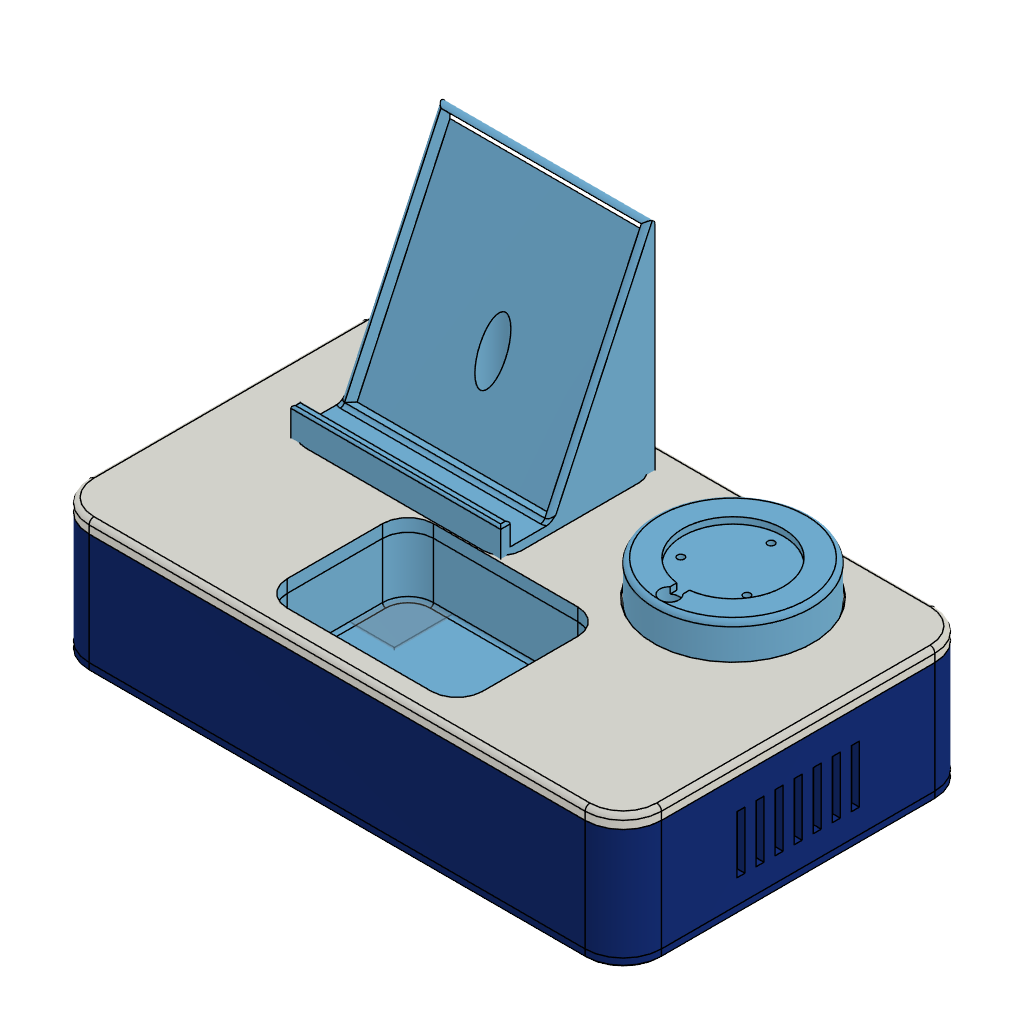
Multi_charge (Autodesk Fusion 360 design; units mm, degrees)
part number: 2026-11-17-23-31-15-888
part number: 2026-11-18-01-23-41-298
part number: 2026-11-18-01-23-42-263
part number: 2026-11-18-01-23-42-966
part number: 2026-11-18-01-29-00-402
part number: 2026-11-18-01-29-01-069
part number: 2026-11-18-01-54-52-643
part number: 2026-11-18-01-54-53-349
part number: 2026-11-18-01-54-56-501
description: REFERENCE ONLY - envelopes, not real STEP models. Do not print.
part number: 2026-11-18-01-54-56-940
description: REFERENCE ONLY - clearance keep-out volumes. Do not print.
part number: 2026-11-18-01-54-57-566
Autodesk Fusion 360 part; units mm, degrees
ref_plane "WorkPlane1" through (0, 0, 2.5) normal (0, 0, 1) x (1, 0, 0) in component "Base_Enclosure"
sketch "Base Outline" plane through (0, 0, 2.5) normal (0, 0, 1) x (1, 0, 0) in component "Base_Enclosure"
  line L0 (-78, -55) -> (78, -55)
  line L1 (90, -43) -> (90, 43)
  line L2 (78, 55) -> (-78, 55)
  line L3 (-90, 43) -> (-90, -43)
  arc A0 (78, -55) -> (90, -43) centre (78, -43) ccw
  arc A1 (90, 43) -> (78, 55) centre (78, 43) ccw
  arc A2 (-78, 55) -> (-90, 43) centre (-78, 43) ccw
  arc A3 (-90, -43) -> (-78, -55) centre (-78, -43) ccw
extrude "Base Extrude" add sketch "Base Outline" along normal blind 35 makes body 1 in component "Base_Enclosure"
shell "Base Shell" thickness 2.4 removed faces 2 at (26, -18.3333, 2.5) at (26, -18.3333, 37.5) on bodies 1 in component "Base_Enclosure"
ref_plane "WorkPlane2" through (0, 0, 8) normal (0, 0, 1) x (1, 0, 0) in component "Base_Enclosure"
sketch "Rib Layout" plane through (0, 0, 8) normal (0, 0, 1) x (1, 0, 0) in component "Base_Enclosure"
  line L0 (-59, -53.8) -> (-57, -53.8)
  line L1 (-57, -53.8) -> (-57, 53.8)
  line L2 (-57, 53.8) -> (-59, 53.8)
  line L3 (-59, 53.8) -> (-59, -53.8)
  line L4 (57, -53.8) -> (59, -53.8)
  line L5 (59, -53.8) -> (59, 53.8)
  line L6 (59, 53.8) -> (57, 53.8)
  line L7 (57, 53.8) -> (57, -53.8)
  line L8 (-88.8, -44) -> (-58, -44)
  line L9 (-58, -44) -> (-58, -42)
  line L10 (-58, -42) -> (-88.8, -42)
  line L11 (-88.8, -42) -> (-88.8, -44)
  line L12 (-88.8, 42) -> (-58, 42)
  line L13 (-58, 42) -> (-58, 44)
  line L14 (-58, 44) -> (-88.8, 44)
  line L15 (-88.8, 44) -> (-88.8, 42)
  line L16 (58, -44) -> (88.8, -44)
  line L17 (88.8, -44) -> (88.8, -42)
  line L18 (88.8, -42) -> (58, -42)
  line L19 (58, -42) -> (58, -44)
  line L20 (58, 42) -> (88.8, 42)
  line L21 (88.8, 42) -> (88.8, 44)
  line L22 (88.8, 44) -> (58, 44)
  line L23 (58, 44) -> (58, 42)
extrude "Structural Ribs" add sketch "Rib Layout" along normal blind 25.5 bodies 1 in component "Base_Enclosure"
ref_plane "WorkPlane1" through (0, 0, 37.5) normal (0, 0, 1) x (1, 0, 0) in component "Upper_Platform"
sketch "Platform Outline" plane through (0, 0, 37.5) normal (0, 0, 1) x (1, 0, 0) in component "Upper_Platform"
  line L0 (-78, -55) -> (78, -55)
  line L1 (90, -43) -> (90, 43)
  line L2 (78, 55) -> (-78, 55)
  line L3 (-90, 43) -> (-90, -43)
  arc A0 (78, -55) -> (90, -43) centre (78, -43) ccw
  arc A1 (90, 43) -> (78, 55) centre (78, 43) ccw
  arc A2 (-78, 55) -> (-90, 43) centre (-78, 43) ccw
  arc A3 (-90, -43) -> (-78, -55) centre (-78, -43) ccw
extrude "Platform Plate" add sketch "Platform Outline" along normal blind 4 separate body makes body 2 in component "Upper_Platform"
sketch "Locating Lip" plane through (0, 0, 37.5) normal (0, 0, 1) x (1, 0, 0) in component "Upper_Platform"
  line L0 (-78, -52.3) -> (78, -52.3)
  line L1 (87.3, -43) -> (87.3, 43)
  line L2 (78, 52.3) -> (-78, 52.3)
  line L3 (-87.3, 43) -> (-87.3, -43)
  arc A0 (78, -52.3) -> (87.3, -43) centre (78, -43) ccw
  arc A1 (87.3, 43) -> (78, 52.3) centre (78, 43) ccw
  arc A2 (-78, 52.3) -> (-87.3, 43) centre (-78, 43) ccw
  arc A3 (-87.3, -43) -> (-78, -52.3) centre (-78, -43) ccw
  line L4 (-78, -50.7) -> (78, -50.7)
  line L5 (85.7, -43) -> (85.7, 43)
  line L6 (78, 50.7) -> (-78, 50.7)
  line L7 (-85.7, 43) -> (-85.7, -43)
  arc A4 (78, -50.7) -> (85.7, -43) centre (78, -43) ccw
  arc A5 (85.7, 43) -> (78, 50.7) centre (78, 43) ccw
  arc A6 (-78, 50.7) -> (-85.7, 43) centre (-78, 43) ccw
  arc A7 (-85.7, -43) -> (-78, -50.7) centre (-78, -43) ccw
extrude "Locating Lip Extrude" add sketch "Locating Lip" against normal blind 3 bodies 2 in component "Upper_Platform"
fillet "Platform Edge Fillet" radius 1.5 64 edges at (-86.4853, -51.4853, 41.5) (0, -55, 41.5) (86.4853, -51.4853, 41.5) (90, 0, 41.5) (86.4853, 51.4853, 41.5) (0, 55, 41.5) (-86.4853, 51.4853, 41.5) (-90, 0, 41.5) (0, -55, 41.5) (86.4853, -51.4853, 41.5) (90, 0, 41.5) (86.4853, 51.4853, 41.5) (0, 55, 41.5) (-86.4853, 51.4853, 41.5) (-90, 0, 41.5) (-86.4853, -51.4853, 41.5) (86.4853, -51.4853, 41.5) (90, 0, 41.5) (86.4853, 51.4853, 41.5) (0, 55, 41.5) (-86.4853, 51.4853, 41.5) (-90, 0, 41.5) (-86.4853, -51.4853, 41.5) (0, -55, 41.5) (90, 0, 41.5) (86.4853, 51.4853, 41.5) (0, 55, 41.5) (-86.4853, 51.4853, 41.5) (-90, 0, 41.5) (-86.4853, -51.4853, 41.5) (0, -55, 41.5) (86.4853, -51.4853, 41.5) (86.4853, 51.4853, 41.5) (0, 55, 41.5) (-86.4853, 51.4853, 41.5) (-90, 0, 41.5) (-86.4853, -51.4853, 41.5) (0, -55, 41.5) (86.4853, -51.4853, 41.5) (90, 0, 41.5) (0, 55, 41.5) (-86.4853, 51.4853, 41.5) (-90, 0, 41.5) (-86.4853, -51.4853, 41.5) (0, -55, 41.5) (86.4853, -51.4853, 41.5) (90, 0, 41.5) (86.4853, 51.4853, 41.5) (-86.4853, 51.4853, 41.5) (-90, 0, 41.5) (-86.4853, -51.4853, 41.5) (0, -55, 41.5) (86.4853, -51.4853, 41.5) (90, 0, 41.5) (86.4853, 51.4853, 41.5) (0, 55, 41.5) (-90, 0, 41.5) (-86.4853, -51.4853, 41.5) (0, -55, 41.5) (86.4853, -51.4853, 41.5) (90, 0, 41.5) (86.4853, 51.4853, 41.5) (0, 55, 41.5) (-86.4853, 51.4853, 41.5) on bodies 2 in component "Upper_Platform"
ref_plane "WorkPlane2" through (0, 0, 41.5) normal (0, 0, 1) x (1, 0, 0) in component "Upper_Platform"
sketch "Charging Zones (phone, watch, earbuds)" plane through (0, 0, 41.5) normal (0, 0, 1) x (1, 0, 0) in component "Upper_Platform"
  line L0 (-63.5, -1.5) -> (-7.5, -1.5)
  line L1 (-1.5, 4.5) -> (-1.5, 41.5)
  line L2 (-7.5, 47.5) -> (-63.5, 47.5)
  line L3 (-69.5, 41.5) -> (-69.5, 4.5)
  arc A0 (-7.5, -1.5) -> (-1.5, 4.5) centre (-7.5, 4.5) ccw
  arc A1 (-1.5, 41.5) -> (-7.5, 47.5) centre (-7.5, 41.5) ccw
  arc A2 (-63.5, 47.5) -> (-69.5, 41.5) centre (-63.5, 41.5) ccw
  arc A3 (-69.5, 4.5) -> (-63.5, -1.5) centre (-63.5, 4.5) ccw
  circle A4 centre (44.5, 25) radius 25
  line L4 (-22, -44) -> (22, -44)
  line L5 (30, -36) -> (30, -14)
  line L6 (22, -6) -> (-22, -6)
  line L7 (-30, -14) -> (-30, -36)
  arc A5 (22, -44) -> (30, -36) centre (22, -36) ccw
  arc A6 (30, -14) -> (22, -6) centre (22, -14) ccw
  arc A7 (-22, -6) -> (-30, -14) centre (-22, -14) ccw
  arc A8 (-30, -36) -> (-22, -44) centre (-22, -36) ccw
extrude "Charging Zone Recesses" cut sketch "Charging Zones (phone, watch, earbuds)" against normal blind 1.2 bodies 2 in component "Upper_Platform"
sketch "Cover Outline" plane through (0, 0, 0) normal (0, 0, 1) x (1, 0, 0) in component "Bottom_Cover"
  line L0 (-78, -55) -> (78, -55)
  line L1 (90, -43) -> (90, 43)
  line L2 (78, 55) -> (-78, 55)
  line L3 (-90, 43) -> (-90, -43)
  arc A0 (78, -55) -> (90, -43) centre (78, -43) ccw
  arc A1 (90, 43) -> (78, 55) centre (78, 43) ccw
  arc A2 (-78, 55) -> (-90, 43) centre (-78, 43) ccw
  arc A3 (-90, -43) -> (-78, -55) centre (-78, -43) ccw
extrude "Cover Plate" add sketch "Cover Outline" along normal blind 2.5 separate body makes body 3 in component "Bottom_Cover"
ref_plane "WorkPlane1" through (0, 0, 2.5) normal (0, 0, 1) x (1, 0, 0) in component "Bottom_Cover"
sketch "Locating Lip (2)" plane through (0, 0, 2.5) normal (0, 0, 1) x (1, 0, 0) in component "Bottom_Cover"
  line L0 (-78, -52.3) -> (78, -52.3)
  line L1 (87.3, -43) -> (87.3, 43)
  line L2 (78, 52.3) -> (-78, 52.3)
  line L3 (-87.3, 43) -> (-87.3, -43)
  arc A0 (78, -52.3) -> (87.3, -43) centre (78, -43) ccw
  arc A1 (87.3, 43) -> (78, 52.3) centre (78, 43) ccw
  arc A2 (-78, 52.3) -> (-87.3, 43) centre (-78, 43) ccw
  arc A3 (-87.3, -43) -> (-78, -52.3) centre (-78, -43) ccw
  line L4 (-78, -50.7) -> (78, -50.7)
  line L5 (85.7, -43) -> (85.7, 43)
  line L6 (78, 50.7) -> (-78, 50.7)
  line L7 (-85.7, 43) -> (-85.7, -43)
  arc A4 (78, -50.7) -> (85.7, -43) centre (78, -43) ccw
  arc A5 (85.7, 43) -> (78, 50.7) centre (78, 43) ccw
  arc A6 (-78, 50.7) -> (-85.7, 43) centre (-78, 43) ccw
  arc A7 (-85.7, -43) -> (-78, -50.7) centre (-78, -43) ccw
extrude "Locating Lip Extrude'" add sketch "Locating Lip (2)" along normal blind 3 bodies 3 in component "Bottom_Cover"
sketch "PCB Standoffs (placeholder envelope)" plane through (0, 0, 2.5) normal (0, 0, 1) x (1, 0, 0) in component "Bottom_Cover"
  circle A0 centre (-46, -31) radius 3.5
  circle A1 centre (-46, -31) radius 1.25
  circle A2 centre (-46, 31) radius 3.5
  circle A3 centre (-46, 31) radius 1.25
  circle A4 centre (46, -31) radius 3.5
  circle A5 centre (46, -31) radius 1.25
  circle A6 centre (46, 31) radius 3.5
  circle A7 centre (46, 31) radius 1.25
extrude "PCB Standoffs" add sketch "PCB Standoffs (placeholder envelope)" along normal blind 8 bodies 3 in component "Bottom_Cover"
ref_plane "WorkPlane1" through (-83, 0, 0) normal (1, 0, 0) x (0, 1, 0) in component "Phone_Holder"
sketch "Holder Side Profile" plane through (-83, 0, 0) normal (1, 0, 0) x (0, 0, -1) in component "Phone_Holder"
  line L0 (-40.3, -1.0742) -> (-40.3, 47.5)
  line L1 (-40.3, 47.5) -> (-115.3, 47.5)
  line L2 (-115.3, 47.5) -> (-43.3, 13.9258)
  line L3 (-43.3, 13.9258) -> (-43.3, 1.9258)
  line L4 (-43.3, 1.9258) -> (-50.3, 1.9258)
  line L5 (-50.3, 1.9258) -> (-50.3, -1.0742)
  line L6 (-50.3, -1.0742) -> (-40.3, -1.0742)
extrude "Holder Body" add sketch "Holder Side Profile" along normal blind 66 separate body makes body 4 in component "Phone_Holder"
fillet "Support Face Fillet" radius 1.5 4 edges at (-83, 30.7129, 79.3) (-50, 13.9258, 43.3) (-17, 30.7129, 79.3) (-50, 47.5, 115.3) on bodies 4 in component "Phone_Holder"
fillet "Retaining Lip Fillet" radius 0.75 4 edges at (-83, 0.4258, 50.3) (-50, -1.0742, 50.3) (-17, 0.4258, 50.3) (-50, 1.9258, 50.3) on bodies 4 in component "Phone_Holder"
sketch "MagSafe Pocket" plane through (0, -5.1463, 2.3997) normal (0, -0.906308, 0.422618) x (0, -0.422618, -0.906308) in component "Phone_Holder"
  line L0 (-46.0841, -81.5) -> (-46.0841, -18.5)
  line L1 (-46.0841, -18.5) -> (-117.8056, -18.5)
  line L2 (-117.8056, -18.5) -> (-117.8056, -81.5)
  line L3 (-117.8056, -81.5) -> (-46.0841, -81.5)
  circle A0 centre (-81.9448, -50) radius 27.75
extrude "MagSafe Pocket Cut" cut sketch "MagSafe Pocket" against normal blind 4.37 contours L0 L1 L2 L3 | A0 bodies 4 in component "Phone_Holder"
ref_plane "WorkPlane2" through (0, 0, 115.3) normal (0, 0, 1) x (1, 0, 0) in component "Phone_Holder"
sketch "Cable Channel" plane through (0, 0, 115.3) normal (0, 0, 1) x (1, 0, 0) in component "Phone_Holder"
  circle A0 centre (-50, 29.4851) radius 4
extrude "Cable Channel (1)" cut sketch "Cable Channel" against normal blind 75 bodies 4 in component "Phone_Holder"
sketch "Phone Cable Port" plane through (0, 0, 41.5) normal (0, 0, 1) x (1, 0, 0) in component "Upper_Platform"
  circle A0 centre (-35.5, 29.4851) radius 4
extrude "Phone Cable Port (1)" cut sketch "Phone Cable Port" against normal blind 4 bodies 2 in component "Upper_Platform"
ref_plane "WorkPlane1" through (0, 0, 40.3) normal (0, 0, 1) x (1, 0, 0) in component "Watch_Holder"
sketch "Watch Pad Outline" plane through (0, 0, 40.3) normal (0, 0, 1) x (1, 0, 0) in component "Watch_Holder"
  circle A0 centre (30, 25) radius 24.5
extrude "Watch Pad" add sketch "Watch Pad Outline" along normal blind 12 separate body makes body 5 in component "Watch_Holder"
fillet "Pad Top Fillet" radius 1.5 1 edges at (7.158, 16.1404, 52.3) on bodies 5 in component "Watch_Holder"
ref_plane "WorkPlane2" through (0, 0, 52.3) normal (0, 0, 1) x (1, 0, 0) in component "Watch_Holder"
sketch "Charging Surface Recess" plane through (0, 0, 52.3) normal (0, 0, 1) x (1, 0, 0) in component "Watch_Holder"
  circle A0 centre (30, 25) radius 15.81
extrude "Charging Surface Recess (1)" cut sketch "Charging Surface Recess" against normal blind 2 bodies 5 in component "Watch_Holder"
sketch "Cable Groove" plane through (0, 0, 52.3) normal (0, 0, 1) x (1, 0, 0) in component "Watch_Holder"
  line L0 (28, 5) -> (32, 5)
  line L1 (32, 5) -> (32, 11.19)
  line L2 (32, 11.19) -> (28, 11.19)
  line L3 (28, 11.19) -> (28, 5)
extrude "Cable Groove Cut" cut sketch "Cable Groove" against normal blind 2 bodies 5 in component "Watch_Holder"
sketch "Cable Passage" plane through (0, 0, 52.3) normal (0, 0, 1) x (1, 0, 0) in component "Watch_Holder"
  circle A0 centre (30, 5) radius 3
extrude "Cable Passage (1)" cut sketch "Cable Passage" against normal blind 12 bodies 5 in component "Watch_Holder"
ref_plane "WorkPlane3" through (0, 0, 50.3) normal (0, 0, 1) x (1, 0, 0) in component "Watch_Holder"
sketch "M2 Mounting Holes" plane through (0, 0, 50.3) normal (0, 0, 1) x (1, 0, 0) in component "Watch_Holder"
  circle A0 centre (30, 37) radius 1.1
  circle A1 centre (19.6077, 19) radius 1.1
  circle A2 centre (40.3923, 19) radius 1.1
extrude "M2 Mounting Holes (1)" cut sketch "M2 Mounting Holes" against normal blind 6 bodies 5 in component "Watch_Holder"
sketch "Watch Cable Port" plane through (0, 0, 41.5) normal (0, 0, 1) x (1, 0, 0) in component "Upper_Platform"
  circle A0 centre (44.5, 5) radius 3
extrude "Watch Cable Port (1)" cut sketch "Watch Cable Port" against normal blind 4 bodies 2 in component "Upper_Platform"
ref_plane "WorkPlane1" through (0, 0, 17) normal (0, 0, 1) x (1, 0, 0) in component "Earbuds_Compartment"
sketch "Tray Outer" plane through (0, 0, 17) normal (0, 0, 1) x (1, 0, 0) in component "Earbuds_Compartment"
  line L0 (1.3, -49.6) -> (46.7, -49.6)
  line L1 (56.3, -40) -> (56.3, -10)
  line L2 (46.7, -0.4) -> (1.3, -0.4)
  line L3 (-8.3, -10) -> (-8.3, -40)
  arc A0 (46.7, -49.6) -> (56.3, -40) centre (46.7, -40) ccw
  arc A1 (56.3, -10) -> (46.7, -0.4) centre (46.7, -10) ccw
  arc A2 (1.3, -0.4) -> (-8.3, -10) centre (1.3, -10) ccw
  arc A3 (-8.3, -40) -> (1.3, -49.6) centre (1.3, -40) ccw
extrude "Tray Outer (1)" add sketch "Tray Outer" along normal blind 20.5 separate body makes body 6 in component "Earbuds_Compartment"
ref_plane "WorkPlane2" through (0, 0, 37.5) normal (0, 0, 1) x (1, 0, 0) in component "Earbuds_Compartment"
sketch "Case Pocket" plane through (0, 0, 37.5) normal (0, 0, 1) x (1, 0, 0) in component "Earbuds_Compartment"
  line L0 (1.3, -48) -> (46.7, -48)
  line L1 (54.7, -40) -> (54.7, -10)
  line L2 (46.7, -2) -> (1.3, -2)
  line L3 (-6.7, -10) -> (-6.7, -40)
  arc A0 (46.7, -48) -> (54.7, -40) centre (46.7, -40) ccw
  arc A1 (54.7, -10) -> (46.7, -2) centre (46.7, -10) ccw
  arc A2 (1.3, -2) -> (-6.7, -10) centre (1.3, -10) ccw
  arc A3 (-6.7, -40) -> (1.3, -48) centre (1.3, -40) ccw
extrude "Case Pocket Cut" cut sketch "Case Pocket" against normal blind 18.5 bodies 6 in component "Earbuds_Compartment"
fillet "Pocket Floor Fillet" radius 1 64 edges at (-4.3569, -45.6569, 19) (-6.7, -25, 19) (-4.3569, -4.3431, 19) (24, -2, 19) (52.3569, -4.3431, 19) (54.7, -25, 19) (52.3569, -45.6569, 19) (24, -48, 19) (24, -48, 19) (-4.3569, -45.6569, 19) (-6.7, -25, 19) (-4.3569, -4.3431, 19) (24, -2, 19) (52.3569, -4.3431, 19) (54.7, -25, 19) (52.3569, -45.6569, 19) (52.3569, -45.6569, 19) (24, -48, 19) (-4.3569, -45.6569, 19) (-6.7, -25, 19) (-4.3569, -4.3431, 19) (24, -2, 19) (52.3569, -4.3431, 19) (54.7, -25, 19) (54.7, -25, 19) (52.3569, -45.6569, 19) (24, -48, 19) (-4.3569, -45.6569, 19) (-6.7, -25, 19) (-4.3569, -4.3431, 19) (24, -2, 19) (52.3569, -4.3431, 19) (52.3569, -4.3431, 19) (54.7, -25, 19) (52.3569, -45.6569, 19) (24, -48, 19) (-4.3569, -45.6569, 19) (-6.7, -25, 19) (-4.3569, -4.3431, 19) (24, -2, 19) (24, -2, 19) (52.3569, -4.3431, 19) (54.7, -25, 19) (52.3569, -45.6569, 19) (24, -48, 19) (-4.3569, -45.6569, 19) (-6.7, -25, 19) (-4.3569, -4.3431, 19) (-4.3569, -4.3431, 19) (24, -2, 19) (52.3569, -4.3431, 19) (54.7, -25, 19) (52.3569, -45.6569, 19) (24, -48, 19) (-4.3569, -45.6569, 19) (-6.7, -25, 19) (-6.7, -25, 19) (-4.3569, -4.3431, 19) (24, -2, 19) (52.3569, -4.3431, 19) (54.7, -25, 19) (52.3569, -45.6569, 19) (24, -48, 19) (-4.3569, -45.6569, 19) on bodies 6 in component "Earbuds_Compartment"
sketch "Earbuds Case Opening" plane through (0, 0, 41.5) normal (0, 0, 1) x (1, 0, 0) in component "Upper_Platform"
  line L0 (-22.7, -48) -> (22.7, -48)
  line L1 (30.7, -40) -> (30.7, -10)
  line L2 (22.7, -2) -> (-22.7, -2)
  line L3 (-30.7, -10) -> (-30.7, -40)
  arc A0 (22.7, -48) -> (30.7, -40) centre (22.7, -40) ccw
  arc A1 (30.7, -10) -> (22.7, -2) centre (22.7, -10) ccw
  arc A2 (-22.7, -2) -> (-30.7, -10) centre (-22.7, -10) ccw
  arc A3 (-30.7, -40) -> (-22.7, -48) centre (-22.7, -40) ccw
extrude "Earbuds Case Opening Cut" cut sketch "Earbuds Case Opening" against normal blind 4 bodies 2 in component "Upper_Platform"
ref_plane "WorkPlane1" through (0, 0, 2.5) normal (0, 0, 1) x (1, 0, 0) in component "PCB_Supports"
ref_plane "WorkPlane2" through (0, 0, 12.85) normal (0, 0, 1) x (1, 0, 0) in component "PCB_Supports"
sketch "QI_Support_1 Post" plane through (0, 0, 2.5) normal (0, 0, 1) x (1, 0, 0) in component "PCB_Supports"
  line L0 (11, -39.6) -> (19, -39.6)
  line L1 (19, -39.6) -> (19, -31)
  line L2 (19, -31) -> (11, -31)
  line L3 (11, -31) -> (11, -39.6)
extrude "QI_Support_1 Post (1)" add sketch "QI_Support_1 Post" along normal blind 10.35 separate body makes body 7 in component "PCB_Supports"
sketch "QI_Support_1 Edge Guide" plane through (0, 0, 12.85) normal (0, 0, 1) x (1, 0, 0) in component "PCB_Supports"
  line L0 (10, -37.5) -> (20, -37.5)
  line L1 (20, -37.5) -> (20, -36.3)
  line L2 (20, -36.3) -> (10, -36.3)
  line L3 (10, -36.3) -> (10, -37.5)
extrude "QI_Support_1 Guide" add sketch "QI_Support_1 Edge Guide" along normal blind 2 bodies 7 in component "PCB_Supports"
sketch "QI_Support_2 Post" plane through (0, 0, 2.5) normal (0, 0, 1) x (1, 0, 0) in component "PCB_Supports"
  line L0 (29, -39.6) -> (37, -39.6)
  line L1 (37, -39.6) -> (37, -31)
  line L2 (37, -31) -> (29, -31)
  line L3 (29, -31) -> (29, -39.6)
extrude "QI_Support_2 Post (1)" add sketch "QI_Support_2 Post" along normal blind 10.35 separate body makes body 8 in component "PCB_Supports"
sketch "QI_Support_2 Edge Guide" plane through (0, 0, 12.85) normal (0, 0, 1) x (1, 0, 0) in component "PCB_Supports"
  line L0 (28, -37.5) -> (38, -37.5)
  line L1 (38, -37.5) -> (38, -36.3)
  line L2 (38, -36.3) -> (28, -36.3)
  line L3 (28, -36.3) -> (28, -37.5)
extrude "QI_Support_2 Guide" add sketch "QI_Support_2 Edge Guide" along normal blind 2 bodies 8 in component "PCB_Supports"
sketch "QI_Support_3 Post" plane through (0, 0, 2.5) normal (0, 0, 1) x (1, 0, 0) in component "PCB_Supports"
  line L0 (11, -19) -> (19, -19)
  line L1 (19, -19) -> (19, -10.4)
  line L2 (19, -10.4) -> (11, -10.4)
  line L3 (11, -10.4) -> (11, -19)
extrude "QI_Support_3 Post (1)" add sketch "QI_Support_3 Post" along normal blind 10.35 separate body makes body 9 in component "PCB_Supports"
sketch "QI_Support_3 Edge Guide" plane through (0, 0, 12.85) normal (0, 0, 1) x (1, 0, 0) in component "PCB_Supports"
  line L0 (10, -13.7) -> (20, -13.7)
  line L1 (20, -13.7) -> (20, -12.5)
  line L2 (20, -12.5) -> (10, -12.5)
  line L3 (10, -12.5) -> (10, -13.7)
extrude "QI_Support_3 Guide" add sketch "QI_Support_3 Edge Guide" along normal blind 2 bodies 9 in component "PCB_Supports"
sketch "QI_Support_4 Post" plane through (0, 0, 2.5) normal (0, 0, 1) x (1, 0, 0) in component "PCB_Supports"
  line L0 (29, -19) -> (37, -19)
  line L1 (37, -19) -> (37, -10.4)
  line L2 (37, -10.4) -> (29, -10.4)
  line L3 (29, -10.4) -> (29, -19)
extrude "QI_Support_4 Post (1)" add sketch "QI_Support_4 Post" along normal blind 10.35 separate body makes body 10 in component "PCB_Supports"
sketch "QI_Support_4 Edge Guide" plane through (0, 0, 12.85) normal (0, 0, 1) x (1, 0, 0) in component "PCB_Supports"
  line L0 (28, -13.7) -> (38, -13.7)
  line L1 (38, -13.7) -> (38, -12.5)
  line L2 (38, -12.5) -> (28, -12.5)
  line L3 (28, -12.5) -> (28, -13.7)
extrude "QI_Support_4 Guide" add sketch "QI_Support_4 Edge Guide" along normal blind 2 bodies 10 in component "PCB_Supports"
sketch "QI_Support_5 Post" plane through (0, 0, 2.5) normal (0, 0, 1) x (1, 0, 0) in component "PCB_Supports"
  line L0 (0.4, -35) -> (9, -35)
  line L1 (9, -35) -> (9, -27)
  line L2 (9, -27) -> (0.4, -27)
  line L3 (0.4, -27) -> (0.4, -35)
extrude "QI_Support_5 Post (1)" add sketch "QI_Support_5 Post" along normal blind 10.35 separate body makes body 11 in component "PCB_Supports"
sketch "QI_Support_5 Edge Guide" plane through (0, 0, 12.85) normal (0, 0, 1) x (1, 0, 0) in component "PCB_Supports"
  line L0 (2.5, -36) -> (3.7, -36)
  line L1 (3.7, -36) -> (3.7, -26)
  line L2 (3.7, -26) -> (2.5, -26)
  line L3 (2.5, -26) -> (2.5, -36)
extrude "QI_Support_5 Guide" add sketch "QI_Support_5 Edge Guide" along normal blind 2 bodies 11 in component "PCB_Supports"
sketch "QI_Support_6 Post" plane through (0, 0, 2.5) normal (0, 0, 1) x (1, 0, 0) in component "PCB_Supports"
  line L0 (39, -23) -> (47.6, -23)
  line L1 (47.6, -23) -> (47.6, -15)
  line L2 (47.6, -15) -> (39, -15)
  line L3 (39, -15) -> (39, -23)
extrude "QI_Support_6 Post (1)" add sketch "QI_Support_6 Post" along normal blind 10.35 separate body makes body 12 in component "PCB_Supports"
sketch "QI_Support_6 Edge Guide" plane through (0, 0, 12.85) normal (0, 0, 1) x (1, 0, 0) in component "PCB_Supports"
  line L0 (44.3, -24) -> (45.5, -24)
  line L1 (45.5, -24) -> (45.5, -14)
  line L2 (45.5, -14) -> (44.3, -14)
  line L3 (44.3, -14) -> (44.3, -24)
extrude "QI_Support_6 Guide" add sketch "QI_Support_6 Edge Guide" along normal blind 2 bodies 12 in component "PCB_Supports"
ref_plane "WorkPlane3" through (0, 0, 2.5) normal (0, 0, 1) x (1, 0, 0) in component "PCB_Supports"
ref_plane "WorkPlane4" through (0, 0, 7.5) normal (0, 0, 1) x (1, 0, 0) in component "PCB_Supports"
sketch "PD_Support_1 Post" plane through (0, 0, 2.5) normal (0, 0, 1) x (1, 0, 0) in component "PCB_Supports"
  line L0 (-47, -21.6) -> (-39, -21.6)
  line L1 (-39, -21.6) -> (-39, -13)
  line L2 (-39, -13) -> (-47, -13)
  line L3 (-47, -13) -> (-47, -21.6)
extrude "PD_Support_1 Post (1)" add sketch "PD_Support_1 Post" along normal blind 5 separate body makes body 13 in component "PCB_Supports"
sketch "PD_Support_1 Edge Guide" plane through (0, 0, 7.5) normal (0, 0, 1) x (1, 0, 0) in component "PCB_Supports"
  line L0 (-48, -19.5) -> (-38, -19.5)
  line L1 (-38, -19.5) -> (-38, -18.3)
  line L2 (-38, -18.3) -> (-48, -18.3)
  line L3 (-48, -18.3) -> (-48, -19.5)
extrude "PD_Support_1 Guide" add sketch "PD_Support_1 Edge Guide" along normal blind 2 bodies 13 in component "PCB_Supports"
sketch "PD_Support_2 Post" plane through (0, 0, 2.5) normal (0, 0, 1) x (1, 0, 0) in component "PCB_Supports"
  line L0 (-31, -21.6) -> (-23, -21.6)
  line L1 (-23, -21.6) -> (-23, -13)
  line L2 (-23, -13) -> (-31, -13)
  line L3 (-31, -13) -> (-31, -21.6)
extrude "PD_Support_2 Post (1)" add sketch "PD_Support_2 Post" along normal blind 5 separate body makes body 14 in component "PCB_Supports"
sketch "PD_Support_2 Edge Guide" plane through (0, 0, 7.5) normal (0, 0, 1) x (1, 0, 0) in component "PCB_Supports"
  line L0 (-32, -19.5) -> (-22, -19.5)
  line L1 (-22, -19.5) -> (-22, -18.3)
  line L2 (-22, -18.3) -> (-32, -18.3)
  line L3 (-32, -18.3) -> (-32, -19.5)
extrude "PD_Support_2 Guide" add sketch "PD_Support_2 Edge Guide" along normal blind 2 bodies 14 in component "PCB_Supports"
sketch "PD_Support_3 Post" plane through (0, 0, 2.5) normal (0, 0, 1) x (1, 0, 0) in component "PCB_Supports"
  line L0 (-47, -3) -> (-39, -3)
  line L1 (-39, -3) -> (-39, 5.6)
  line L2 (-39, 5.6) -> (-47, 5.6)
  line L3 (-47, 5.6) -> (-47, -3)
extrude "PD_Support_3 Post (1)" add sketch "PD_Support_3 Post" along normal blind 5 separate body makes body 15 in component "PCB_Supports"
sketch "PD_Support_3 Edge Guide" plane through (0, 0, 7.5) normal (0, 0, 1) x (1, 0, 0) in component "PCB_Supports"
  line L0 (-48, 2.3) -> (-38, 2.3)
  line L1 (-38, 2.3) -> (-38, 3.5)
  line L2 (-38, 3.5) -> (-48, 3.5)
  line L3 (-48, 3.5) -> (-48, 2.3)
extrude "PD_Support_3 Guide" add sketch "PD_Support_3 Edge Guide" along normal blind 2 bodies 15 in component "PCB_Supports"
sketch "PD_Support_4 Post" plane through (0, 0, 2.5) normal (0, 0, 1) x (1, 0, 0) in component "PCB_Supports"
  line L0 (-31, -3) -> (-23, -3)
  line L1 (-23, -3) -> (-23, 5.6)
  line L2 (-23, 5.6) -> (-31, 5.6)
  line L3 (-31, 5.6) -> (-31, -3)
extrude "PD_Support_4 Post (1)" add sketch "PD_Support_4 Post" along normal blind 5 separate body makes body 16 in component "PCB_Supports"
sketch "PD_Support_4 Edge Guide" plane through (0, 0, 7.5) normal (0, 0, 1) x (1, 0, 0) in component "PCB_Supports"
  line L0 (-32, 2.3) -> (-22, 2.3)
  line L1 (-22, 2.3) -> (-22, 3.5)
  line L2 (-22, 3.5) -> (-32, 3.5)
  line L3 (-32, 3.5) -> (-32, 2.3)
extrude "PD_Support_4 Guide" add sketch "PD_Support_4 Edge Guide" along normal blind 2 bodies 16 in component "PCB_Supports"
sketch "PD_Support_5 Post" plane through (0, 0, 2.5) normal (0, 0, 1) x (1, 0, 0) in component "PCB_Supports"
  line L0 (-54.6, -12) -> (-46, -12)
  line L1 (-46, -12) -> (-46, -4)
  line L2 (-46, -4) -> (-54.6, -4)
  line L3 (-54.6, -4) -> (-54.6, -12)
extrude "PD_Support_5 Post (1)" add sketch "PD_Support_5 Post" along normal blind 5 separate body makes body 17 in component "PCB_Supports"
sketch "PD_Support_5 Edge Guide" plane through (0, 0, 7.5) normal (0, 0, 1) x (1, 0, 0) in component "PCB_Supports"
  line L0 (-52.5, -13) -> (-51.3, -13)
  line L1 (-51.3, -13) -> (-51.3, -3)
  line L2 (-51.3, -3) -> (-52.5, -3)
  line L3 (-52.5, -3) -> (-52.5, -13)
extrude "PD_Support_5 Guide" add sketch "PD_Support_5 Edge Guide" along normal blind 2 bodies 17 in component "PCB_Supports"
sketch "PD_Support_6 Post" plane through (0, 0, 2.5) normal (0, 0, 1) x (1, 0, 0) in component "PCB_Supports"
  line L0 (-24, -12) -> (-15.4, -12)
  line L1 (-15.4, -12) -> (-15.4, -4)
  line L2 (-15.4, -4) -> (-24, -4)
  line L3 (-24, -4) -> (-24, -12)
extrude "PD_Support_6 Post (1)" add sketch "PD_Support_6 Post" along normal blind 5 separate body makes body 18 in component "PCB_Supports"
sketch "PD_Support_6 Edge Guide" plane through (0, 0, 7.5) normal (0, 0, 1) x (1, 0, 0) in component "PCB_Supports"
  line L0 (-18.7, -13) -> (-17.5, -13)
  line L1 (-17.5, -13) -> (-17.5, -3)
  line L2 (-17.5, -3) -> (-18.7, -3)
  line L3 (-18.7, -3) -> (-18.7, -13)
extrude "PD_Support_6 Guide" add sketch "PD_Support_6 Edge Guide" along normal blind 2 bodies 18 in component "PCB_Supports"
ref_plane "WorkPlane1" through (0, 0, 2.5) normal (0, 0, 1) x (1, 0, 0) in component "Cable_Routing"
sketch "Duct_PD_to_QI" plane through (0, 0, 2.5) normal (0, 0, 1) x (1, 0, 0) in component "Cable_Routing"
  line L0 (-14, -17.6) -> (0, -17.6)
  line L1 (0, -17.6) -> (0, -16)
  line L2 (0, -16) -> (-14, -16)
  line L3 (-14, -16) -> (-14, -17.6)
  line L4 (-14, -8) -> (0, -8)
  line L5 (0, -8) -> (0, -6.4)
  line L6 (0, -6.4) -> (-14, -6.4)
  line L7 (-14, -6.4) -> (-14, -8)
extrude "Duct_PD_to_QI (1)" add sketch "Duct_PD_to_QI" along normal blind 5 separate body makes body 19 at (-4.6667, -16, 4.1667) makes body 20 at (-4.6667, -6.4, 4.1667) in component "Cable_Routing"
ref_plane "WorkPlane2" through (0, 0, 2.5) normal (0, 0, 1) x (1, 0, 0) in component "Cable_Routing"
sketch "Duct_USB_Input_to_PD" plane through (0, 0, 2.5) normal (0, 0, 1) x (1, 0, 0) in component "Cable_Routing"
  line L0 (-85, -13.6) -> (-56, -13.6)
  line L1 (-56, -13.6) -> (-56, -12)
  line L2 (-56, -12) -> (-85, -12)
  line L3 (-85, -12) -> (-85, -13.6)
  line L4 (-85, -4) -> (-56, -4)
  line L5 (-56, -4) -> (-56, -2.4)
  line L6 (-56, -2.4) -> (-85, -2.4)
  line L7 (-85, -2.4) -> (-85, -4)
extrude "Duct_USB_Input_to_PD (1)" add sketch "Duct_USB_Input_to_PD" along normal blind 5 separate body makes body 21 at (-65.6667, -12, 4.1667) makes body 22 at (-65.6667, -2.4, 4.1667) in component "Cable_Routing"
ref_plane "WorkPlane1" through (0, 0, 12.85) normal (0, 0, 1) x (1, 0, 0) in component "Reference_Envelopes"
sketch "REF_LinkCom_QI2QT-6130A1_PCB_40x22x2.5 (envelope)" plane through (0, 0, 12.85) normal (0, 0, 1) x (1, 0, 0) in component "Reference_Envelopes"
  line L0 (4, -36) -> (44, -36)
  line L1 (44, -36) -> (44, -14)
  line L2 (44, -14) -> (4, -14)
  line L3 (4, -14) -> (4, -36)
extrude "REF_LinkCom_QI2QT-6130A1_PCB_40x22x2.5 (envelope) (1)" add sketch "REF_LinkCom_QI2QT-6130A1_PCB_40x22x2.5 (envelope)" along normal blind 2.5 separate body makes body 23 in component "Reference_Envelopes"
ref_plane "WorkPlane2" through (0, 0, 15.35) normal (0, 0, 1) x (1, 0, 0) in component "Reference_Envelopes"
sketch "REF_Coil_and_Shield_D43.5x1.65 (envelope)" plane through (0, 0, 15.35) normal (0, 0, 1) x (1, 0, 0) in component "Reference_Envelopes"
  circle A0 centre (24, -25) radius 21.75
extrude "REF_Coil_and_Shield_D43.5x1.65 (envelope) (1)" add sketch "REF_Coil_and_Shield_D43.5x1.65 (envelope)" along normal blind 1.65 separate body makes body 24 in component "Reference_Envelopes"
ref_plane "WorkPlane3" through (0, 0, 7.5) normal (0, 0, 1) x (1, 0, 0) in component "Reference_Envelopes"
sketch "REF_HESTORE_PD65W-M_PCB_32x20x9.1max (envelope)" plane through (0, 0, 7.5) normal (0, 0, 1) x (1, 0, 0) in component "Reference_Envelopes"
  line L0 (-51, -18) -> (-19, -18)
  line L1 (-19, -18) -> (-19, 2)
  line L2 (-19, 2) -> (-51, 2)
  line L3 (-51, 2) -> (-51, -18)
extrude "REF_HESTORE_PD65W-M_PCB_32x20x9.1max (envelope) (1)" add sketch "REF_HESTORE_PD65W-M_PCB_32x20x9.1max (envelope)" along normal blind 9.1 separate body makes body 25 in component "Reference_Envelopes"
ref_plane "WorkPlane1" through (0, 0, 7.5) normal (0, 0, 1) x (1, 0, 0) in component "Component_Clearance"
sketch "KEEPOUT_PD65W-M_component_clearance" plane through (0, 0, 7.5) normal (0, 0, 1) x (1, 0, 0) in component "Component_Clearance"
  line L0 (-53, -20) -> (-17, -20)
  line L1 (-17, -20) -> (-17, 4)
  line L2 (-17, 4) -> (-53, 4)
  line L3 (-53, 4) -> (-53, -20)
extrude "KEEPOUT_PD65W-M_component_clearance (1)" add sketch "KEEPOUT_PD65W-M_component_clearance" along normal blind 12.1 separate body makes body 26 in component "Component_Clearance"
ref_plane "WorkPlane2" through (0, 0, 2.5) normal (0, 0, 1) x (1, 0, 0) in component "Component_Clearance"
sketch "KEEPOUT_QI2QT_underside_clearance" plane through (0, 0, 2.5) normal (0, 0, 1) x (1, 0, 0) in component "Component_Clearance"
  line L0 (2, -38) -> (46, -38)
  line L1 (46, -38) -> (46, -12)
  line L2 (46, -12) -> (2, -12)
  line L3 (2, -12) -> (2, -38)
extrude "KEEPOUT_QI2QT_underside_clearance (1)" add sketch "KEEPOUT_QI2QT_underside_clearance" along normal blind 10.35 separate body makes body 27 in component "Component_Clearance"
ref_plane "WorkPlane3" through (-91, 0, 0) normal (1, 0, 0) x (0, 1, 0) in component "Base_Enclosure"
sketch "Left Wall Openings (UNVERIFIED placeholders)" plane through (-91, 0, 0) normal (1, 0, 0) x (0, 0, -1) in component "Base_Enclosure"
  line L0 (-12.7, -11) -> (-12.7, -5)
  line L1 (-9.3, -5) -> (-9.3, -11)
  arc A0 (-9.3, -5) -> (-12.7, -5) centre (-11, -5) ccw
  arc A1 (-12.7, -11) -> (-9.3, -11) centre (-11, -11) ccw
  line L2 (-7.75, 2) -> (-14.25, 2)
  line L3 (-14.25, 2) -> (-14.25, 16)
  line L4 (-14.25, 16) -> (-7.75, 16)
  line L5 (-7.75, 16) -> (-7.75, 2)
  line L6 (-6.25, -40.25) -> (-19.75, -40.25)
  line L7 (-19.75, -40.25) -> (-19.75, -29.75)
  line L8 (-19.75, -29.75) -> (-6.25, -29.75)
  line L9 (-6.25, -29.75) -> (-6.25, -40.25)
  circle A2 centre (-11, -21) radius 4
  circle A3 centre (-11, 26) radius 1.6
extrude "Left Wall Openings (USB-C, USB-A, DC, switch, LED - UNVERIFIED)" cut sketch "Left Wall Openings (UNVERIFIED placeholders)" along normal blind 5 bodies 1 in component "Base_Enclosure"
ref_plane "WorkPlane4" through (91, 0, 0) normal (1, 0, 0) x (0, 1, 0) in component "Base_Enclosure"
sketch "Right Wall Vent Slots" plane through (91, 0, 0) normal (1, 0, 0) x (0, 0, -1) in component "Base_Enclosure"
  line L0 (-10, -19.25) -> (-28, -19.25)
  line L1 (-28, -19.25) -> (-28, -16.75)
  line L2 (-28, -16.75) -> (-10, -16.75)
  line L3 (-10, -16.75) -> (-10, -19.25)
  line L4 (-10, -13.25) -> (-28, -13.25)
  line L5 (-28, -13.25) -> (-28, -10.75)
  line L6 (-28, -10.75) -> (-10, -10.75)
  line L7 (-10, -10.75) -> (-10, -13.25)
  line L8 (-10, -7.25) -> (-28, -7.25)
  line L9 (-28, -7.25) -> (-28, -4.75)
  line L10 (-28, -4.75) -> (-10, -4.75)
  line L11 (-10, -4.75) -> (-10, -7.25)
  line L12 (-10, -1.25) -> (-28, -1.25)
  line L13 (-28, -1.25) -> (-28, 1.25)
  line L14 (-28, 1.25) -> (-10, 1.25)
  line L15 (-10, 1.25) -> (-10, -1.25)
  line L16 (-10, 4.75) -> (-28, 4.75)
  line L17 (-28, 4.75) -> (-28, 7.25)
  line L18 (-28, 7.25) -> (-10, 7.25)
  line L19 (-10, 7.25) -> (-10, 4.75)
  line L20 (-10, 10.75) -> (-28, 10.75)
  line L21 (-28, 10.75) -> (-28, 13.25)
  line L22 (-28, 13.25) -> (-10, 13.25)
  line L23 (-10, 13.25) -> (-10, 10.75)
  line L24 (-10, 16.75) -> (-28, 16.75)
  line L25 (-28, 16.75) -> (-28, 19.25)
  line L26 (-28, 19.25) -> (-10, 19.25)
  line L27 (-10, 19.25) -> (-10, 16.75)
extrude "Ventilation Slots (right wall)" cut sketch "Right Wall Vent Slots" against normal blind 5 bodies 1 in component "Base_Enclosure"
ref_plane "WorkPlane5" through (0, 0, 2.5) normal (0, 0, 1) x (1, 0, 0) in component "Base_Enclosure"
sketch "Cover Screw Bosses" plane through (0, 0, 2.5) normal (0, 0, 1) x (1, 0, 0) in component "Base_Enclosure"
  circle A0 centre (78, 43) radius 3.5
  circle A1 centre (78, -43) radius 3.5
  circle A2 centre (-78, 43) radius 3.5
  circle A3 centre (-78, -43) radius 3.5
extrude "Cover Screw Bosses (M3)" add sketch "Cover Screw Bosses" along normal blind 29.5 bodies 1 in component "Base_Enclosure"
ref_plane "WorkPlane6" through (0, 0, 6) normal (0, 0, 1) x (1, 0, 0) in component "Base_Enclosure"
sketch "Boss Webs" plane through (0, 0, 6) normal (0, 0, 1) x (1, 0, 0) in component "Base_Enclosure"
  line L0 (76.5, 43) -> (79.5, 43)
  line L1 (79.5, 43) -> (79.5, 53.5)
  line L2 (79.5, 53.5) -> (76.5, 53.5)
  line L3 (76.5, 53.5) -> (76.5, 43)
  line L4 (76.5, -43) -> (79.5, -43)
  line L5 (79.5, -43) -> (79.5, -53.5)
  line L6 (79.5, -53.5) -> (76.5, -53.5)
  line L7 (76.5, -53.5) -> (76.5, -43)
  line L8 (-79.5, 43) -> (-76.5, 43)
  line L9 (-76.5, 43) -> (-76.5, 53.5)
  line L10 (-76.5, 53.5) -> (-79.5, 53.5)
  line L11 (-79.5, 53.5) -> (-79.5, 43)
  line L12 (-79.5, -43) -> (-76.5, -43)
  line L13 (-76.5, -43) -> (-76.5, -53.5)
  line L14 (-76.5, -53.5) -> (-79.5, -53.5)
  line L15 (-79.5, -53.5) -> (-79.5, -43)
extrude "Boss Webs (1)" add sketch "Boss Webs" along normal blind 26 bodies 1 in component "Base_Enclosure"
sketch "Boss Pilot Holes" plane through (0, 0, 2.5) normal (0, 0, 1) x (1, 0, 0) in component "Base_Enclosure"
  circle A0 centre (78, 43) radius 1.25
  circle A1 centre (78, -43) radius 1.25
  circle A2 centre (-78, 43) radius 1.25
  circle A3 centre (-78, -43) radius 1.25
extrude "Boss Pilot Holes (M3 self-tap)" cut sketch "Boss Pilot Holes" along normal blind 15 bodies 1 in component "Base_Enclosure"
chamfer "Cover Bottom Edge Chamfer 0.5 mm" distance 0.5 angle 45 8 edges at (-86.4853, -51.4853, 0) (0, -55, 0) (86.4853, -51.4853, 0) (90, 0, 0) (86.4853, 51.4853, 0) (0, 55, 0) (-86.4853, 51.4853, 0) (-90, 0, 0) tangent chain off on bodies 3 in component "Bottom_Cover"
sketch "Cover Screw Clearance Holes (M3, 3.4 mm)" plane through (0, 0, 0) normal (0, 0, 1) x (1, 0, 0) in component "Bottom_Cover"
  circle A0 centre (78, 43) radius 1.7
  circle A1 centre (78, -43) radius 1.7
  circle A2 centre (-78, 43) radius 1.7
  circle A3 centre (-78, -43) radius 1.7
extrude "Cover Screw Clearance Holes (M3, 3.4 mm) (1)" cut sketch "Cover Screw Clearance Holes (M3, 3.4 mm)" along normal blind 2.5 bodies 3 in component "Bottom_Cover"
sketch "Cover Screw Counterbores (6.0 mm x 1.4 mm)" plane through (0, 0, 0) normal (0, 0, 1) x (1, 0, 0) in component "Bottom_Cover"
  circle A0 centre (78, 43) radius 3
  circle A1 centre (78, -43) radius 3
  circle A2 centre (-78, 43) radius 3
  circle A3 centre (-78, -43) radius 3
extrude "Cover Screw Counterbores (6.0 mm x 1.4 mm) (1)" cut sketch "Cover Screw Counterbores (6.0 mm x 1.4 mm)" along normal blind 1.4 bodies 3 in component "Bottom_Cover"
sketch "Non-slip Foot Recesses (10.2 mm x 1.0 mm)" plane through (0, 0, 0) normal (0, 0, 1) x (1, 0, 0) in component "Bottom_Cover"
  circle A0 centre (60, 32) radius 5.1
  circle A1 centre (60, -32) radius 5.1
  circle A2 centre (-60, 32) radius 5.1
  circle A3 centre (-60, -32) radius 5.1
extrude "Non-slip Foot Recesses (10.2 mm x 1.0 mm) (1)" cut sketch "Non-slip Foot Recesses (10.2 mm x 1.0 mm)" along normal blind 1 bodies 3 in component "Bottom_Cover"
component "Base_Enclosure" placed x (1, 0, 0) y (0, 1, 0) z (0, 0, 1) at (0, 0, 0)
component "Upper_Platform" placed x (1, 0, 0) y (0, 1, 0) z (0, 0, 1) at (0, 0, 0)
component "Bottom_Cover" placed x (1, 0, 0) y (0, 1, 0) z (0, 0, 1) at (0, 0, 0)
component "Phone_Holder" placed x (1, 0, 0) y (0, 1, 0) z (0, 0, 1) at (14.5, 0, 0)
component "Watch_Holder" placed x (1, 0, 0) y (0, 1, 0) z (0, 0, 1) at (14.5, 0, 0)
component "Earbuds_Compartment" placed x (1, 0, 0) y (0, 1, 0) z (0, 0, 1) at (-24, 0, 0)
component "PCB_Supports" placed x (1, 0, 0) y (0, 1, 0) z (0, 0, 1) at (0, 0, 0)
component "Cable_Routing" placed x (1, 0, 0) y (0, 1, 0) z (0, 0, 1) at (0, 0, 0)
component "Reference_Envelopes" placed x (1, 0, 0) y (0, 1, 0) z (0, 0, 1) at (0, 0, 0)
component "Component_Clearance" placed x (1, 0, 0) y (0, 1, 0) z (0, 0, 1) at (0, 0, 0)
equation "Base_Length = 180 mm" comment "Outer length X"
equation "Base_Width = 110 mm" comment "Outer width Y"
equation "Base_Height = 35 mm" comment "Base shell height"
equation "Corner_Radius = 12 mm" comment "Vertical corner radius"
equation "Wall_T = 2.4 mm" comment "Wall thickness (6 x 0.4 mm perimeters)"
equation "Cover_T = 2.5 mm" comment "Bottom cover plate thickness"
equation "Platform_T = 4 mm" comment "Upper platform thickness"
equation "Lip_Height = 3 mm" comment "Locating lip height"
equation "Lip_Wall = 1.6 mm" comment "Locating lip wall thickness"
equation "Fit_Clearance = 0.3 mm" comment "Print fit clearance for lips"
equation "Edge_Fillet = 1.5 mm" comment "Platform top edge fillet"
equation "Zone_Depth = 1.2 mm" comment "Charging zone recess depth"
equation "Rib_T = 2 mm" comment "Internal rib thickness"
equation "Rib_Start_Z = 8 mm" comment "Rib bottom height above origin plane"
equation "Rib_Height = 25.5 mm" comment "Internal rib height"
equation "PCB_Length = 100 mm" comment "PLACEHOLDER PCB envelope - replace with real board"
equation "PCB_Width = 70 mm" comment "PLACEHOLDER PCB envelope - replace with real board"
equation "Standoff_OD = 7 mm" comment "PCB standoff outer diameter"
equation "Standoff_Pilot = 2.5 mm" comment "PCB standoff pilot hole - set per screw or insert"
equation "Standoff_H = 8 mm" comment "PCB standoff height"
equation "Standoff_Inset = 4 mm" comment "Standoff centre inset from PCB envelope edge"
equation "d22 = Cover_T"
equation "d24 = Base_Height"
equation "d26 = Wall_T"
equation "d27 = Rib_Start_Z"
equation "d29 = Rib_Height"
equation "d31 = Cover_T + Base_Height"
equation "d33 = Platform_T"
equation "d35 = -Lip_Height"
equation "d38 = Edge_Fillet"
equation "d39 = Cover_T + Base_Height + Platform_T"
equation "d41 = -Zone_Depth"
equation "d43 = Cover_T"
equation "d45 = Cover_T"
equation "d47 = Lip_Height"
equation "d49 = Standoff_H"
equation "Phone_Zone_X = -50 mm" comment "Phone holder centre X (matches phone zone)"
equation "Holder_Width = 66 mm" comment "Phone holder width (fits phone zone)"
equation "Holder_Rise = 75 mm" comment "Phone holder rear height above recess floor"
equation "Tilt_Angle = 65 deg" comment "Support face angle from horizontal"
equation "Holder_Plate_T = 3 mm" comment "Holder floor plate thickness"
equation "Rest_Gap = 12 mm" comment "PLACEHOLDER lip-to-support gap - set from phone thickness plus case"
equation "Lip_T = 3 mm" comment "Bottom retaining lip thickness"
equation "Lip_H = 10 mm" comment "Bottom retaining lip height"
equation "Holder_Fillet = 1.5 mm" comment "Holder edge fillet"
equation "MagSafe_D = 55.5 mm" comment "MagSafe pocket diameter"
equation "MagSafe_Depth = 4.37 mm" comment "MagSafe pocket depth"
equation "Cable_Channel_D = 8 mm" comment "Phone cable channel diameter"
equation "Watch_Zone_X = 30 mm" comment "Watch holder centre X (matches watch zone)"
equation "Watch_Zone_Y = 25 mm" comment "Watch holder centre Y (matches watch zone)"
equation "Watch_Pad_D = 49 mm" comment "Watch pad diameter (zone is 50)"
equation "Watch_Pad_H = 12 mm" comment "Watch pad height above recess floor"
equation "Watch_Surface_D = 31.62 mm" comment "Charging surface diameter"
equation "Watch_Surface_Depth = 2 mm" comment "PLACEHOLDER charging surface recess depth"
equation "Watch_Bolt_Circle_D = 24 mm" comment "PLACEHOLDER M2 bolt circle - set from C162 drawing"
equation "M2_Hole_D = 2.2 mm" comment "M2 hole diameter"
equation "M2_Hole_Depth = 6 mm" comment "PLACEHOLDER M2 hole depth"
equation "Watch_Cable_D = 6 mm" comment "Watch cable passage diameter"
equation "Watch_Cable_Offset = 20 mm" comment "Cable passage offset from pad centre toward -Y"
equation "Watch_Groove_W = 4 mm" comment "Cable groove width"
equation "d75 = Phone_Zone_X - Holder_Width / 2"
equation "d77 = Holder_Width"
equation "d80 = Holder_Fillet"
equation "d82 = Holder_Fillet / 2"
equation "d83 = -MagSafe_Depth"
equation "d85 = Cover_T + Base_Height + Platform_T - Zone_Depth + Holder_Rise"
equation "d87 = -Holder_Rise"
equation "d89 = -Platform_T"
equation "d91 = Cover_T + Base_Height + Platform_T - Zone_Depth"
equation "d93 = Watch_Pad_H"
equation "d96 = Holder_Fillet"
equation "d97 = Cover_T + Base_Height + Platform_T - Zone_Depth + Watch_Pad_H"
equation "d99 = -Watch_Surface_Depth"
equation "d101 = -Watch_Surface_Depth"
equation "d103 = -Watch_Pad_H"
equation "d105 = Cover_T + Base_Height + Platform_T - Zone_Depth + Watch_Pad_H - Watch_Surface_Depth"
equation "d107 = -M2_Hole_Depth"
equation "d109 = -Platform_T"
equation "Case_L = 60.6 mm" comment "AirPods Pro 2 case length"
equation "Case_W = 45.2 mm" comment "AirPods Pro 2 case width"
equation "Case_H = 21.7 mm" comment "AirPods Pro 2 case height"
equation "Case_Clear = 0.4 mm" comment "PLACEHOLDER clearance per side around case"
equation "Case_Top_Gap = 0.8 mm" comment "Case top sits this far below platform surface"
equation "Case_Corner_R = 8 mm" comment "PLACEHOLDER case plan-view corner radius"
equation "Tray_Wall = 1.6 mm" comment "Earbuds tray wall thickness"
equation "Tray_Floor_T = 2 mm" comment "Earbuds tray floor thickness"
equation "Tray_Fillet = 1 mm" comment "Tray pocket floor fillet"
equation "Earbud_X = 24 mm" comment "Earbuds compartment centre X"
equation "Earbud_Y = -25 mm" comment "Earbuds compartment centre Y"
equation "Qi_L = 40 mm" comment "LinkCom QI2QT-6130A1 PCB length (reference envelope)"
equation "Qi_W = 22 mm" comment "LinkCom QI2QT-6130A1 PCB width (reference envelope)"
equation "Qi_T = 2.5 mm" comment "LinkCom QI2QT-6130A1 PCB thickness (reference envelope)"
equation "Coil_D = 43.5 mm" comment "Coil and shielding diameter (assumed from 43.5 x 1.65)"
equation "Coil_T = 1.65 mm" comment "Coil and shielding thickness"
equation "PD_L = 32 mm" comment "HESTORE PD65W-M PCB length (reference envelope)"
equation "PD_W = 20 mm" comment "HESTORE PD65W-M PCB width (reference envelope)"
equation "PD_H = 9.1 mm" comment "HESTORE PD65W-M maximum height"
equation "PD_X = -35 mm" comment "PD PCB centre X"
equation "PD_Y = -8 mm" comment "PD PCB centre Y"
equation "PD_Support_H = 5 mm" comment "PD PCB underside clearance height above cover"
equation "Keepout_Side = 2 mm" comment "Component clearance around PCB sides"
equation "Keepout_Top = 3 mm" comment "Component clearance above PD PCB"
equation "Guide_H = 2 mm" comment "Edge guide height above board bottom"
equation "Guide_Clear = 0.3 mm" comment "Edge guide clearance to board edge"
equation "Guide_Wall = 1.2 mm" comment "Edge guide wall thickness"
equation "Duct_W = 8 mm" comment "Cable duct inner width"
equation "Duct_Wall = 1.6 mm" comment "Cable duct wall thickness"
equation "Duct_H = 5 mm" comment "Cable duct wall height"
equation "Tray_Floor_Bottom_Z = Cover_T + Base_Height + Platform_T - Case_H - Case_Top_Gap - Tray_Floor_T" comment "Derived stack height"
equation "Qi_Z = Tray_Floor_Bottom_Z - Coil_T - Qi_T" comment "Derived stack height"
equation "PD_Z = Cover_T + PD_Support_H" comment "Derived stack height"
equation "d144 = Tray_Floor_Bottom_Z"
equation "d146 = Case_H + Case_Top_Gap + Tray_Floor_T - Platform_T"
equation "d148 = Cover_T + Base_Height"
equation "d150 = -( Case_H + Case_Top_Gap - Platform_T )"
equation "d153 = Tray_Fillet"
equation "d154 = -Platform_T"
equation "d156 = Cover_T"
equation "d158 = Qi_Z"
equation "d160 = Qi_Z - Cover_T"
equation "d162 = Guide_H"
equation "d164 = Qi_Z - Cover_T"
equation "d166 = Guide_H"
equation "d168 = Qi_Z - Cover_T"
equation "d170 = Guide_H"
equation "d172 = Qi_Z - Cover_T"
equation "d174 = Guide_H"
equation "d176 = Qi_Z - Cover_T"
equation "d178 = Guide_H"
equation "d180 = Qi_Z - Cover_T"
equation "d182 = Guide_H"
equation "d184 = Cover_T"
equation "d186 = PD_Z"
equation "d188 = PD_Support_H"
equation "d190 = Guide_H"
equation "d192 = PD_Support_H"
equation "d194 = Guide_H"
equation "d196 = PD_Support_H"
equation "d198 = Guide_H"
equation "d200 = PD_Support_H"
equation "d202 = Guide_H"
equation "d204 = PD_Support_H"
equation "d206 = Guide_H"
equation "d208 = PD_Support_H"
equation "d210 = Guide_H"
equation "d212 = Cover_T"
equation "d214 = Duct_H"
equation "d216 = Cover_T"
equation "d218 = Duct_H"
equation "d220 = Qi_Z"
equation "d222 = Qi_T"
equation "d224 = Qi_Z + Qi_T"
equation "d226 = Coil_T"
equation "d228 = PD_Z"
equation "d230 = PD_H"
equation "d232 = PD_Z"
equation "d234 = PD_H + Keepout_Top"
equation "d236 = Cover_T"
equation "d238 = Qi_Z - Cover_T"
named bodies: "Base_Body", "Platform_Body", "Cover_Body", "Phone_Holder_Body", "Watch_Holder_Body", "Earbuds_Tray_Body", "QI_Support_1", "QI_Support_2", "QI_Support_3", "QI_Support_4", "QI_Support_5", "QI_Support_6", "PD_Support_1", "PD_Support_2", "PD_Support_3", "PD_Support_4", "PD_Support_5", "PD_Support_6", "Duct_PD_to_QI_Wall_1", "Duct_PD_to_QI_Wall_2", "Duct_USB_Input_to_PD_Wall_1", "Duct_USB_Input_to_PD_Wall_2", "REF_LinkCom_QI2QT-6130A1_PCB_40x22x2.5 (envelope)", "REF_Coil_and_Shield_D43.5x1.65 (envelope)", "REF_HESTORE_PD65W-M_PCB_32x20x9.1max (envelope)", "KEEPOUT_PD65W-M_component_clearance", "KEEPOUT_QI2QT_underside_clearance"
